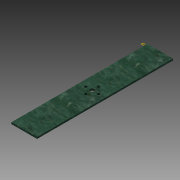
# Autodesk Inventor part: Yaw_Back
Saved by Autodesk Inventor 2013 (Build 170138000, 138)
## iProperties
Created: 2013-09-30
Part Number: Yaw_Back
Material: Generic
Document SubType Name: Modeling
Designer: Jeff
Density: 1 g/cm^3
Author: Jeff
Autodesk Inventor part; units mm, degrees
ref_plane "YZ Plane" through (0, 0, 0) normal (1, 0, 0) x (0, 1, 0)
ref_plane "XZ Plane" through (0, 0, 0) normal (0, 1, 0) x (-1, 0, 0)
ref_plane "XY Plane" through (0, 0, 0) normal (0, 0, 1) x (1, 0, 0)
ref_plane "Work Plane1" through (0, 0, 0) normal (0, 0, 1) x (1, 0, 0)
sketch "Sketch1" plane through (0, 0, 0) normal (0, 0, 1) x (1, 0, 0)
  line L0 (3.0209, 1.5875) -> (27.0209, 1.5875)
  line L1 (27.0209, 1.5875) -> (27.0209, -125.675)
  line L2 (27.0209, -125.675) -> (3.0209, -125.675)
  line L3 (3.0209, -125.675) -> (3.0209, 1.5875)
  circle A0 centre (15.0209, -68.0438) radius 1.25
  circle A1 centre (21.0209, -62.0438) radius 1.25
  circle A2 centre (15.0209, -56.0437) radius 1.25
  circle A3 centre (9.0209, -62.0438) radius 1.25
  line L4 (15.0209, 1.5875) -> (15.0209, -125.675)
  line L5 (27.0209, -62.0438) -> (3.0209, -62.0438)
  point P0 (15.0209, -62.0438)
  dimension "d5" = 360
  dimension "d1" = 2.5
  dimension "d17" = 24
  dimension "d18" = 12
  constraints: 12 end point, 4 centre point, 2 horizontal, 2 parallel, 1 perpendicular, 1 vertical, 2 other
  measures "d1" diameter of A0
  measures "d17" distance between parallel lines of L3 L1
  measures "d18" distance of A2.centre A0.centre
extrude "Extrusion1" add sketch "Sketch1" along normal blind 1.5875 contours L0 L4 A2 L5 A3 L3 | L0 L1 L5 A1 L4 A2 | L5 A3 L4 A0 L2 L3 | L1 L2 L4 A0 L5 A1
sketch "Sketch2" plane through (0, 0, 1.5875) normal (0, 0, 1) x (1, 0, 0)
  circle A0 centre (15.0209, -62.0438) radius 2
  line L0 (9.0209, -62.0438) -> (21.0209, -62.0438)
  line L1 (15.0209, -68.0438) -> (15.0209, -56.0437)
  point P0 (0, 0)
  point P1 (15.0209, -62.0438)
  dimension "d9" = 4
  constraints: 4 end point, 1 centre point
  measures "d9" diameter of A0
hole "Hole1" at (15.0209, -62.0438, 1.5875) direction (0, 0, -1) diameter 4 end through all
body "Solid1"
